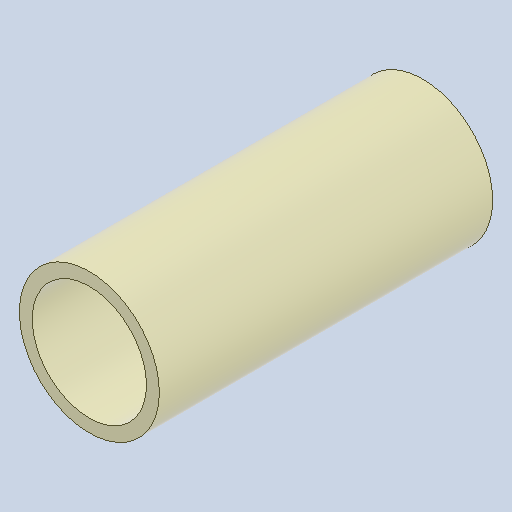
# Autodesk Inventor part: RDS-1104 Outlet Pipe PP
Saved by Autodesk Inventor 2026.2 (Build 302298000, 298)
## iProperties
Created: 2026-10-18
Part Number: RDS-1104 Outlet Pipe PP
Material: Polypropylene
Description: Outlet pipe PP d63, placeholder
Document SubType Name: Modeling
Designer: admin
Stock Number: Патрубок выхода ПП (размер уточнить)
Density: 0.899 g/cm^3
Appearance: Smooth - Ash
Author: admin
Autodesk Inventor part; units mm, degrees
ref_plane "YZ Plane" through (0, 0, 0) normal (1, 0, 0) x (0, 1, 0)
ref_plane "XZ Plane" through (0, 0, 0) normal (0, 1, 0) x (-1, 0, 0)
ref_plane "XY Plane" through (0, 0, 0) normal (0, 0, 1) x (1, 0, 0)
sketch "Sketch1" plane through (0, 0, 0) normal (0, 0, 1) x (1, 0, 0)
  circle A0 centre (0, 0) radius 31.5
  circle A1 centre (0, 0) radius 25.7
  dimension "d0" = 63
  dimension "d1" = 51.4
  constraints: 2 centre point
  measures "d0" diameter of A0
  measures "d1" diameter of A1
extrude "Extrusion1" add sketch "Sketch1" along normal blind 150
equation "\"d0\" = Pipe1104_Outer_Diam"
equation "\"d1\" = Pipe1104_Inner_Diam"
equation "\"d2\" = Pipe1104_Length"
equation "\"Pipe1104_Outer_Diam\" = 63"
equation "\"Pipe1104_Inner_Diam\" = 51.4"
equation "\"Pipe1104_Length\" = 150"
body "Solid1"
